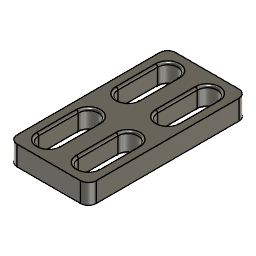
Skadense Customizable Size (Autodesk Fusion 360 design; units mm, degrees)
Autodesk Fusion 360 part; units mm, degrees
sketch "Szkic1" plane through (0, 0, 0) normal (0, 0, 1) x (1, 0, 0)
  line L0 (0, 0) -> (20, 0)
  line L1 (20, 0) -> (20, 40)
  line L2 (20, 40) -> (0, 40)
  line L3 (0, 40) -> (0, 0)
  dimension "d9" = 20
  dimension "d10" = 40
  constraint horizontal L0
  constraint vertical L1
  constraint horizontal L2
  constraint vertical L3
  constraint coincident L0.start L3.end
  measures "d9" distance of L0.start L0.end
  measures "d10" distance of L0.start L2.end
extrude "Wyciągnięcie proste1" add sketch "Szkic1" along normal blind 5
sketch "Szkic2" plane through (0, 0, 5) normal (0, 0, 1) x (-1, 0, 0)
  line L0 (0, -40) -> (0, 0)
  line L1 (0, 0) -> (-20, 0)
  line L2 (-20, 0) -> (-20, -40)
  line L3 (-20, -40) -> (0, -40)
  line L4 (-7.5, -15) -> (-7.5, -5)
  line L5 (-2.5, -5) -> (-2.5, -15)
  arc A0 (-5, -17.5) -> (-2.5, -15) centre (-5, -15) ccw
  arc A1 (-7.5, -15) -> (-5, -17.5) centre (-5, -15) ccw
  arc A2 (-2.5, -5) -> (-5, -2.5) centre (-5, -5) ccw
  arc A3 (-5, -2.5) -> (-7.5, -5) centre (-5, -5) ccw
  arc A4 (-2.45, -5) -> (-5, -2.45) centre (-5, -5) ccw
  arc A5 (-5, -2.45) -> (-7.55, -5) centre (-5, -5) ccw
  line L6 (-7.55, -15) -> (-7.55, -5)
  arc A6 (-7.55, -15) -> (-5, -17.55) centre (-5, -15) ccw
  arc A7 (-5, -17.55) -> (-2.45, -15) centre (-5, -15) ccw
  line L7 (-2.45, -5) -> (-2.45, -15)
  point P0 (-2.5, -17.5)
  point P1 (-7.5, -17.5)
  point P2 (-2.5, -2.5)
  dimension "d13" = 5
  dimension "d14" = 15
  dimension "d15" = 2.5
  dimension "d17" = 2.5
  dimension "d18" = -0.05
  constraint vertical L4
  constraint vertical L5
  constraint coincident P0 L5
  constraint tangent L5 A0
  constraint coincident P1 L4
  constraint tangent L4 A1
  constraint equal A0 A1
  constraint coincident A0.start A1.end
  constraint coincident P2 L5
  constraint tangent L5 A2
  constraint equal A0 A2
  constraint tangent L4 A3
  constraint equal A0 A3
  constraint coincident A2.end A3.start
  measures "d13" distance of P0 P1
  measures "d14" distance of P0 P2
  measures "d15" distance of L0 L5
  measures "d17" radius of A0
extrude "Wyciągnięcie proste2" cut sketch "Szkic2" against normal blind 5 contours L4 L5 A0 A1 A2 A3 | A4 A5 L6 A6 A7 L7
fillet "Zaokrąglenie1" radius 0.5 8 edges at (5, 2.45, 0) (7.55, 10, 0) (5, 17.55, 0) (2.45, 10, 0) (5, 2.45, 5) (2.45, 10, 5) (5, 17.55, 5) (7.55, 10, 5)
pattern_linear "Szyk prostokątny1" count 2 spacing 10 along (1, 0, 0) count 2 spacing 20 along (0, 1, 0) of "Wyciągnięcie proste2", "Zaokrąglenie1"
fillet "Zaokrąglenie2" radius 2 4 edges at (0, 0, 2.5) (20, 0, 2.5) (20, 40, 2.5) (0, 40, 2.5)
move_body "Przesuń1" bodies 1 to x (1, 0, 0) y (0, 1, 0) z (0, 0, 1) at (-125, -125, 0)
move_body "Przesuń2" bodies 1 to x (1, 0, 0) y (0, 1, 0) z (0, 0, 1) at (0, 20, 0)
equation "Width = 20 mm"
equation "Height = 40 mm"
equation "Thickness = 5 mm"
equation "Pattern_Offset = 2.5 mm"
equation "Columns = Width / 10 mm"
equation "Columns_Distance = 10 mm"
equation "Rows_Distance = 20 mm"
equation "d9 = Width"
equation "d10 = Height"
equation "d11 = Thickness"
equation "d15 = Pattern_Offset"
equation "d19 = -Thickness"
equation "Rows = Height / 20 mm"
equation "d24 = Columns"
equation "d25 = Rows"
equation "d26 = Columns_Distance"
equation "d27 = Rows_Distance"
